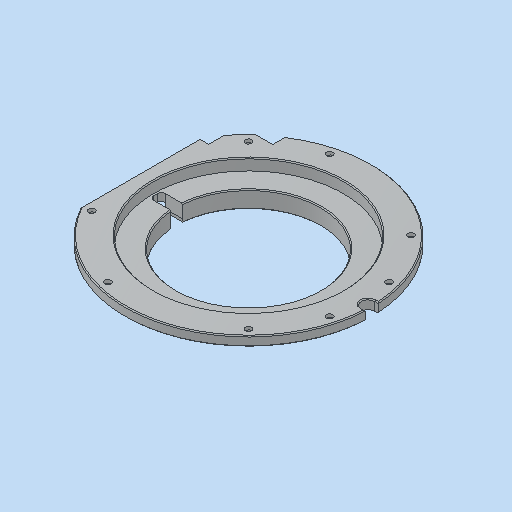
# Autodesk Inventor part: MM0948AN100_G01_117
Saved by Autodesk Inventor 2023.3 (Build 273359000, 359)
## iProperties
Part Number: MM0948AN100_G01_117
Material: 3.3547 AlMg4,5Mn0,7 - AW 5083
Description: =<RBPARTNOTITLE2>
Document SubType Name: Modeling
Designer: ric7an
Mass: 154.283 g
Surface Area: 253.435 cm^2
Volume: 57.1418 cm^3
Density: 2.7 g/cm^3
Appearance: Aluminium AnP
Created: 2023-03-23
RBDOCUMENTTYPE: DRF
RBDOCUMENTVERSION: 00
RBDRAWINGMAINSCALE: 1:1
RBDRAWINGMISSINGSPEC: --
RBDRAWINGVOLUME: --
RBGBEDGESIN1: +0,5
RBGBEDGESIN2: +0,2
RBGBEDGESOUT1: -0,3
RBGBEDGESOUT2: -0,1
RBMATERIAL: =<Material>
RBMATMEETS: --
RBMATNO: =<Part Number>
RBPARTMADEOF: Rd. 130 x 15 (FM)
RBPARTNO: SIEHE MNR
RBPARTNOTITLE1: manufactured part
RBPARTNOTITLE2: Anfertigungsteil
RBPARTSAFETYINDICATOR: --
RBSURFACE: hard-coated  475 HV ± 25, 40 μm coating thickness
RBSURFACE2: hartcoatiert 475 HV ± 25, 40 μm Schicht
RBZEDGESNORM: ISO13715:2002-06
RBZGENDIMCLASS: m
RBZGENDIMNORM: ISO 2768-1:1989-11
RBZGENGEOCLASS: H
RBZGENGEONORM: ISO 2768-2:1989-11
RBZSURFACENORM: ISO13D2:2002-02
RBZTOLERANCENORM: ISO 14405-1:2010-12
AnP_Material: =<Material>
AnP_TemplVers: 20190222
AnP_Kategorie: 1
MaxAbmaße: 121,906 x 15 x 130 (FM)
AnP_Kommentar_aktuell: =<Comments>
AnP_Material_aktuell: =<Material>
Author: FH/Wi
Keywords: =<RBPARTMADEOF>
Comments: =<RBSURFACE2>
Revision Number: 01
Autodesk Inventor part; units mm, degrees
ref_plane "XZ Plane" through (0, 0, 0) normal (0, 1, 0) x (-1, 0, 0)
ref_plane "XY Plane" through (0, 0, 0) normal (0, 0, 1) x (1, 0, 0)
sketch "Skizze1" plane through (0, 0, 0) normal (0, 0, 1) x (1, 0, 0)
  line L0 (0, 18) -> (0, -3) projected
  line L1 (-78, 0) -> (13, 0) projected
  line L2 (0, 15) -> (-56, 15)
  line L3 (-56, 15) -> (-56, 10)
  line L4 (-54.6011, 5) -> (-47, 5)
  line L5 (-45.6011, 0) -> (0, 0)
  line L6 (0, 0) -> (0, 15)
  line L7 (-56, 15) -> (-65, 15)
  line L8 (-65, 15) -> (-65, 10)
  line L9 (-65, 10) -> (-56, 10)
  line L10 (-56, 10) -> (-56, 15)
  line L11 (-56, 10) -> (-56, 8)
  line L12 (-56, 8) -> (-54.6011, 5)
  line L13 (-47, 5) -> (-47, 3)
  line L14 (-47, 3) -> (-45.6011, 0)
  point P0 (0, 0)
  dimension "d3" = 5
  dimension "d4" = 5
  dimension "d5" = 15
  dimension "d30" = 47
  dimension "d31" = 56
  dimension "d32" = 65
  dimension "d33" = 115
  dimension "d34" = 2
  dimension "d35" = 2
  constraints: 26 end point, 4 parallel, 3 perpendicular, 3 vertical, 2 horizontal, 2 point on line, 1 collinear
  measures "d3" vertical distance of L4.end L5.start
  measures "d4" vertical distance of L3.end L4.start
  measures "d5" distance between parallel lines of L1 L2
  measures "d30" distance from line of L0 L4.end
  measures "d31" distance from line of L0 L3.end
  measures "d32" distance between parallel lines of L6 L8
  measures "d33" angle of L1 L14
  measures "d34" distance of L4.end L13.end
  measures "d35" distance of L9.end L11.end
revolve "Umdrehung1" add sketch "Skizze1" angle 360 about axis through (0, 0, 0) along (0, 1, 0)
sketch "Skizze2" plane through (0, 10, 0) normal (0, 1, 0) x (1, 0, 0)
  circle A0 centre (0, 0) radius 60.5 construction
  line L0 (0, 0) -> (52.3945, -30.25) construction
  line L1 (0, 0) -> (-52.3945, -30.25) construction
  line L2 (0, 0) -> (0, 60.5) construction
  line L3 (0, 91) -> (0, -91) projected
  line L4 (91, 0) -> (-91, 0) projected
  point P0 (58.4385, -15.6586)
  point P1 (30.25, -52.3945)
  point P2 (-58.4385, -15.6586)
  point P3 (-42.78, -42.78)
  point P4 (15.6586, 58.4385)
  point P5 (-15.6586, 58.4385)
  point P6 (-42.78, -42.78)
  point P7 (-42.78, 42.78)
  point P8 (42.78, 42.78)
  point P9 (0, 60.5)
  point P10 (30.25, -52.3945)
  dimension "d7" = 121
  dimension "d8" = 30
  dimension "d10" = 30
  dimension "d11" = 120
  dimension "d12" = 120
  dimension "d95" = 45
  dimension "d96" = 90
  dimension "d110" = 75
  dimension "d113" = 90
  dimension "d114" = 60
  dimension "d115" = 45
  constraints: 6 end point, 3 coincident, 3 symmetric about line, 15 other
  measures "d11" angle of L1 L0
  measures "d12" angle of L2 L1
hole "Bohrung1" at (58.4385, 10, 15.6586) at (30.25, 10, 52.3945) at (-58.4385, 10, 15.6586) at (-42.78, 10, 42.78) at (15.6586, 10, -58.4385) at (-15.6586, 10, -58.4385) at (42.78, 10, -42.78) at (-42.78, 10, -42.78) direction (0, 1, 0) diameter 3.4 end through all counterbore diameter 6.5 counterbore depth 3.4 clearance for "Inbusschraube ISO 4762  versenkt" size "M3" standard "ISO"
sketch "Skizze6" plane through (0, 15, 0) normal (0, 1, 0) x (1, 0, 0)
  circle A0 centre (0, 0) radius 65 projected
  line L0 (-3.5, 64.9057) -> (-3.5, 62.9057)
  arc A1 (-3.5, 62.9057) -> (3.5, 62.9057) centre (0, 62.9057) ccw
  line L1 (3.5, 62.9057) -> (3.5, 64.9057)
  line L2 (0, 91) -> (0, -91) projected
  dimension "d36" = 7
  dimension "d37" = 2
  constraints: 4 end point, 4 point on circle, 2 tangent, 1 centre point, 1 parallel, 1 vertical, 1 other
  measures "d36" distance between parallel lines of L1 L0
  measures "d37" distance of L1.start L1.end
extrude "Extrusion4" cut sketch "Skizze6" against normal through all contours L1 A1 L2 A0 | L2 A1 L0 A0 picked at (1.1165, 63.3863) picked at (-1.1165, 63.3863)
sketch "Skizze8" plane through (0, 0, 0) normal (1, 0, 0) x (0, 1, 0)
  line L0 (10, 65) -> (15, 65)
  line L1 (15, 65) -> (15, 57)
  line L2 (15, 57) -> (10, 57)
  line L3 (10, 57) -> (10, 65)
  line L4 (10, 65) -> (15, 65) projected
  line L5 (10, -64.9057) -> (10, 65) projected
  line L6 (15, -64.9057) -> (15, 65) projected
  point P0 (0, 0)
  point P1 (10, -64.9102)
  dimension "d57" = 8
  constraints: 8 end point, 3 collinear, 2 parallel, 1 horizontal, 1 perpendicular
  measures "d57" distance between parallel lines of L0 L2
extrude "Extrusion5" cut sketch "Skizze8" along normal through all both and the other way through all
sketch "Skizze9" plane through (0, 15, -62.9057) normal (0, 1, 0) x (1, 0, 0)
  point P0 (0, -62.9057)
  point P1 (0, -62.9057)
  constraints: 1 coincident
hole "Bohrung3" at (0, 15, 0) direction (0, -1, 0) diameter 60 end through all
sketch "Skizze10" plane through (0, 15, -62.9057) normal (0, 1, 0) x (1, 0, 0)
  circle A0 centre (0, -62.9057) radius 50
  circle A1 centre (0, -62.9057) radius 56 projected
  circle A2 centre (0, -62.9057) radius 54.6011 projected
  dimension "d67" = 100
  constraints: 1 centre point, 1 coincident
  measures "d67" diameter of A0
extrude "Extrusion6" cut sketch "Skizze10" against normal blind 6 contours A0
chamfer "Fase4" distance 0.5 angle 45 3 edges at (0, 15, -59.4057) (-3.5, 15, -63.9057) (3.5, 15, -63.9057)
ref_plane "Arbeitsebene2" through (-31.241, 15, 57) normal (1, 0, 0) x (0, 1, 0)
sketch "Skizze14" plane through (0, 15, -62.9057) normal (0, 1, 0) x (1, 0, 0)
  circle A0 centre (0, -62.9057) radius 45.6011 projected
  circle A1 centre (0, -62.9057) radius 50 projected
  circle A2 centre (0, -62.9057) radius 30 projected
  line L0 (15, -36.9249) -> (22.8005, -23.414)
  line L1 (-15, -36.9249) -> (-22.8005, -23.414)
  line L2 (0, 26.3811) -> (0, -144.2868) projected
  line L3 (91, -62.9057) -> (-91, -62.9057) projected
  arc A3 (-19, -29.9967) -> (19, -29.9967) centre (0, -62.9057) ccw
  arc A4 (-15, -36.9249) -> (15, -36.9249) centre (0, -62.9057) ccw
  arc A5 (19, -29.9967) -> (-19, -29.9967) centre (0, -62.9057) ccw
  dimension "d84" = 300
  dimension "d85" = 30
  dimension "d88" = 38
  constraints: 10 point on circle, 4 end point, 3 centre point, 3 coincident, 3 point on line, 2 line through centre
  measures "d85" angle of L2 L0
  measures "d88" radius of A3
extrude "Extrusion11" cut sketch "Skizze14" against normal through all contours A3 L2 A2 L3 | L3 A2 L0 A3 | L0 A2 L2 A5 | A3 L3 A2 L2 | L2 A2 L1 A5 | A3 L1 A2 L3
sketch "Skizze15" plane through (0, 15, -62.9057) normal (0, 1, 0) x (1, 0, 0)
  line L0 (-51, -114.9057) -> (-31, -114.9057)
  line L1 (-31, -114.9057) -> (-31, -134.9057)
  line L2 (-31, -134.9057) -> (-51, -134.9057)
  line L3 (-51, -134.9057) -> (-51, -114.9057)
  line L4 (0, 29.3811) -> (0, -162.2868) projected
  line L5 (91, -62.9057) -> (-91, -62.9057) projected
  point P0 (0, -62.9057)
  dimension "d99" = 52
  dimension "d100" = 31
  dimension "d101" = 20
  dimension "d102" = 20
  constraints: 8 end point, 2 parallel, 1 horizontal, 1 perpendicular
  measures "d99" distance between parallel lines of L5 L0
  measures "d100" distance between parallel lines of L4 L1
  measures "d101" distance of L1.end L2.end
  measures "d102" distance of L2.end L0.start
extrude "Extrusion12" cut sketch "Skizze15" against normal through all
sketch "Skizze16" plane through (0, 15, -62.9057) normal (0, 1, 0) x (1, 0, 0)
  arc A0 (-4, 1.9711) -> (-39, -114.9057) centre (0, -62.9057) ccw projected
  line L0 (-54.7723, -97.9057) -> (-47.7723, -97.9057)
  line L1 (-47.7723, -97.9057) -> (-47.7723, -117.9057)
  line L2 (-47.7723, -117.9057) -> (-54.7723, -117.9057)
  line L3 (-54.7723, -117.9057) -> (-54.7723, -97.9057)
  line L4 (0, 40.9965) -> (0, -146.7227) projected
  line L5 (93.9536, -62.9057) -> (-108.7215, -62.9057) projected
  dimension "d105" = 7
  dimension "d106" = 20
  dimension "d109" = 35
  constraints: 8 end point, 2 parallel, 1 horizontal, 1 perpendicular, 1 point on circle
  measures "d105" distance of L0.start L0.end
  measures "d106" distance of L0.end L1.end
  measures "d109" distance between parallel lines of L5 L0
extrude "Extrusion13" cut sketch "Skizze16" against normal through all
chamfer "Fase6" distance 0.5 angle 45 10 edges at (-50, 15, 0) (63.4348, 15, -14.1785) (-57.943, 15, -29.4552) (0.1205, 15, 57) (0.1205, 10, 57) (-43.5666, 10, 48.2385) (63.3797, 10, -14.4228) (-57.8291, 10, -29.6783) (-19, 0, 32.909) (-19, 9, 32.909)
sketch "Skizze26" plane through (0, 0, 0) normal (0, 0, 1) x (1, 0, 0)
  line L0 (-38.5, 0) -> (38.5, 0) projected
  line L1 (38.5, 9) -> (-38.5, 9) projected
  line L2 (0, 10.8) -> (0, -1.8) projected
  line L3 (47, 5) -> (-47, 5) projected
  line L4 (54.6011, 5) -> (-54.6011, 5) projected
  line L5 (-3.1, 9) -> (3.1, 9)
  line L6 (3.1, 9) -> (3.1, 0)
  line L7 (3.1, 0) -> (-3.1, 0)
  line L8 (-3.1, 0) -> (-3.1, 9)
  point P0 (-3.1, 0)
  point P1 (3.1, 0)
  dimension "d179" = 6.2
  constraints: 8 end point, 2 parallel, 1 collinear, 1 horizontal, 1 perpendicular, 1 point on line, 1 other
  measures "d179" distance between parallel lines of L6 L8
extrude "Extrusion22" cut sketch "Skizze26" along normal blind 49
chamfer "Fase11" distance 2 angle 15 1 edges at (-3.1, 0, 41.9353) measured on face at (-3.1, 0.5, 41.9353)
chamfer "Fase12" distance 2 angle 15 1 edges at (3.1, 0, 41.9353) measured on face at (3.1, 0.5, 41.9353)
fillet "Rundung5" radius 2 2 edges at (3.1, 7, 49) (-3.1, 7, 49)
equation "\"d10\" = d8"
equation "\"d12\" = d11"
